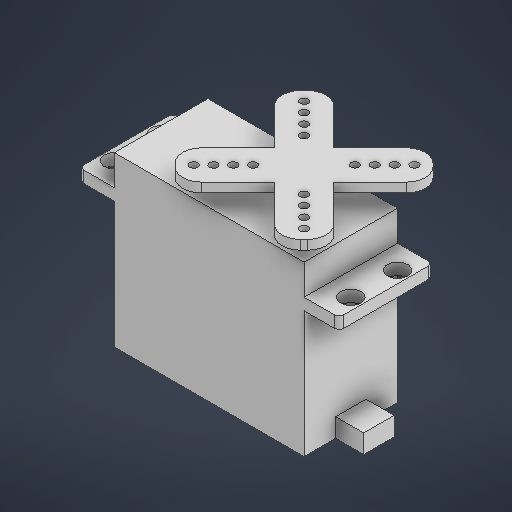
# Autodesk Inventor part: Servo motor
Saved by Autodesk Inventor 2027 (Build 310192000, 192)
## iProperties
Created: 2026-08-31
Part Number: Servo motor
Material: Generic
Document SubType Name: Modeling
Designer: Johannes
Density: 1 g/cm^3
Appearance: Default
Author: Johannes
Autodesk Inventor part; units mm, degrees
ref_plane "YZ Plane" through (0, 0, 0) normal (1, 0, 0) x (0, 1, 0)
ref_plane "XZ Plane" through (0, 0, 0) normal (0, 1, 0) x (-1, 0, 0)
sketch "Sketch1" plane through (0, 0, 0) normal (0, 1, 0) x (-1, 0, 0)
  line L0 (0, 0) -> (40.56, 0)
  line L1 (40.56, 0) -> (40.56, -20)
  line L2 (40.56, -20) -> (0, -20)
  line L3 (0, -20) -> (0, 0)
  dimension "d0" = 40.56
  dimension "d1" = 20
  constraints: 8 end point, 2 parallel, 1 horizontal, 1 perpendicular
  measures "d0" distance of L1.end L2.end
  measures "d1" distance of L0.end L1.end
extrude "Extrusion1" add sketch "Sketch1" along normal blind 36
sketch "Sketch2" plane through (0, 36, 0) normal (0, 1, 0) x (1, 0, 0)
  line L0 (0, 0) -> (-10, 0)
  line L1 (-10, 0) -> (-10, 10)
  line L2 (-10, 10) -> (0, 10)
  line L3 (0, 10) -> (0, 0)
  circle A0 centre (-10, 10) radius 4
  dimension "d4" = 10
  dimension "d5" = 10
  dimension "d6" = 8
  constraints: 8 end point, 2 parallel, 1 centre point, 1 coincident, 1 horizontal, 1 perpendicular
  measures "d4" distance of L1.end L2.end
  measures "d5" distance of L0.end L1.end
  measures "d6" diameter of A0
extrude "Extrusion2" add sketch "Sketch2" along normal blind 8 contours A0 L2 L1 | L1 L2 A0
sketch "Sketch3" plane through (-10, 44, -10) normal (0, 1, 0) x (1, 0, 0)
  circle A0 centre (0, 0) radius 4 projected
  line L0 (0, 0) -> (-13.7886, 13.7886)
  line L1 (0, 0) -> (19.5, 0) construction
  line L2 (-13.7886, 13.7886) -> (-10.6066, 16.9706)
  line L3 (-10.6066, 16.9706) -> (3.182, 3.182)
  line L4 (3.182, 3.182) -> (0, 0)
  line L5 (0, 0) -> (-3.182, -3.182)
  line L6 (-3.182, -3.182) -> (-16.9706, 10.6066)
  line L7 (-16.9706, 10.6066) -> (-13.7886, 13.7886)
  point P0 (10, -10)
  point P1 (-2.8284, -2.8284)
  point P2 (2.8284, 2.8284)
  dimension "d9" = 19.5
  dimension "d10" = 135
  dimension "d11" = 4.5
  dimension "d12" = 4.5
  constraints: 16 end point, 4 perpendicular, 2 point on line, 1 equal length, 1 horizontal
  measures "d9" distance of L0.start L0.end
  measures "d10" angle of L1 L0
  measures "d11" distance of L0.end L2.end
  measures "d12" distance of L0.start L5.end
extrude "Extrusion3" add sketch "Sketch3" against normal blind 2 contours A0 L0 L2 L3 L4 | L5 L6 L7 L0 A0
pattern_circular "Circular Pattern1" count 4 over 360 about axis through (-10, 36, -10) along (0, 1, 0) of "Extrusion3"
fillet "Fillet1" radius 4 8 edges at (-26.9706, 43, 0.6066) (-20.6066, 43, 6.9706) (0.6066, 43, 6.9706) (6.9706, 43, 0.6066) (6.9706, 43, -20.6066) (0.6066, 43, -26.9706) (-20.6066, 43, -26.9706) (-26.9706, 43, -20.6066)
sketch "Sketch4" plane through (0, 44, 0) normal (0, 1, 0) x (1, 0, 0)
  line L0 (3.435, -4.1421) -> (4.1421, -3.435) projected
  line L1 (3.7886, -3.7886) -> (1.8087, -1.8087)
  line L2 (3.7886, -3.7886) -> (6.5886, -3.7886) construction
  circle A0 centre (1.8087, -1.8087) radius 0.86
  point P0 (0, 0)
  dimension "d19" = 2.8
  dimension "d20" = 135
  dimension "d21" = 1.72
  constraints: 4 end point, 1 centre point, 1 coincident, 1 equal length, 1 horizontal, 1 midpoint, 1 perpendicular
  measures "d19" distance of L1.start L1.end
  measures "d20" angle of L2 L1
  measures "d21" diameter of A0
extrude "Extrusion4" cut sketch "Sketch4" against normal blind 3
pattern_linear "Rectangular Pattern1" count 4 spacing 3 along (-0.7071, 0, -0.7071) of "Extrusion4"
pattern_circular "Circular Pattern2" count 4 over 360 about axis through (-10, 36, -10) along (0, 1, 0) of "Extrusion4", "Rectangular Pattern1"
sketch "Sketch5" plane through (0, 0, 0) normal (1, 0, 0) x (0, 0, -1)
  line L0 (0, 0) -> (0, 27)
  line L1 (0, 0) -> (0, 36) projected
  line L2 (20, 0) -> (20, 36) projected
  line L3 (0, 27) -> (20, 27)
  line L4 (20, 27) -> (20, 29.5)
  line L5 (20, 29.5) -> (0, 29.5)
  line L6 (0, 29.5) -> (0, 27)
  dimension "d30" = 27
  dimension "d31" = 2.5
  constraints: 10 end point, 2 parallel, 1 collinear, 1 horizontal, 1 perpendicular, 1 point on line
  measures "d30" distance of L0.start L0.end
  measures "d31" distance of L4.end L3.end
extrude "Extrusion5" add sketch "Sketch5" along normal blind 7.5
sketch "Sketch6" plane through (0, 29.5, 0) normal (0, 1, 0) x (1, 0, 0)
  line L0 (0, 0) -> (0, 20) projected
  line L1 (7.5, 20) -> (7.5, 0) projected
  line L2 (0, 20) -> (7.5, 20) projected
  point P0 (5, 15)
  dimension "d42" = 2.5
  dimension "d43" = 5
  measures "d42" distance from line of point (5, 15) L1
  measures "d43" distance from line of point (5, 15) L2
hole "Hole1" at (5, 29.5, -15) direction (0, -1, 0) diameter 4.3 end through all
pattern_linear "Rectangular Pattern2" count 2 spacing 10 along (0, 0, 1) of "Hole1"
ref_plane "Work Plane1" through (-20.28, 0, 0) normal (1, 0, 0) x (0, 0, -1)
mirror "Mirror1" about plane through (-20.28, 0, 0) normal (1, 0, 0) of "Extrusion5", "Hole1", "Rectangular Pattern2"
fillet "Fillet2" radius 1 4 edges at (-48.06, 28.25, 0) (-48.06, 28.25, -20) (7.5, 28.25, -20) (7.5, 28.25, 0)
sketch "Sketch7" plane through (0, 0, 0) normal (1, 0, 0) x (0, 0, -1)
  line L0 (0, 0) -> (10, 0)
  line L1 (20, 0) -> (0, 0) projected
  line L2 (10, 0) -> (10, 4)
  line L3 (10, 4) -> (13.25, 4)
  line L4 (13.25, 4) -> (13.25, 0)
  line L5 (13.25, 0) -> (10, 0)
  line L6 (10, 4) -> (6.75, 4)
  line L7 (6.75, 4) -> (6.75, 0)
  line L8 (6.75, 0) -> (10, 0)
  dimension "d48" = 10
  dimension "d49" = 4
  dimension "d50" = 3.25
  constraints: 16 end point, 2 parallel, 2 perpendicular, 2 symmetric about line, 1 midpoint
  measures "d48" distance of L0.start L0.end
  measures "d49" distance of L0.end L2.end
  measures "d50" distance of L2.end L3.end
extrude "Extrusion6" add sketch "Sketch7" along normal blind 6
body "Solid1"
